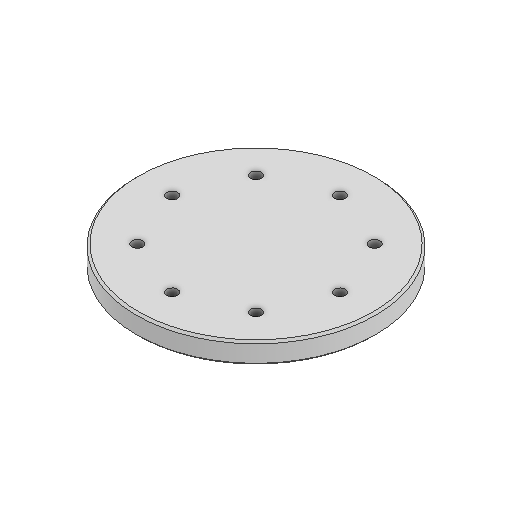
# Autodesk Inventor part: 3DP_PLA_A_Axis_Rotating_Stage_Mounting_Plate
Saved by Autodesk Inventor 2027 (Build 310192060, 192F)
## iProperties
Created: 2026-01-06
Part Number: 3DP_PLA_A_Axis_Rotating_Stage_Mounting_Plate
Material: Generic
Document SubType Name: Modeling
Designer: User
Density: 1 g/cm^3
Appearance: Default
Author: User
Autodesk Inventor part; units mm, degrees
ref_plane "YZ Plane" through (0, 0, 0) normal (1, 0, 0) x (0, 1, 0)
ref_plane "XZ Plane" through (0, 0, 0) normal (0, 1, 0) x (-1, 0, 0)
ref_plane "XY Plane" through (0, 0, 0) normal (0, 0, 1) x (1, 0, 0)
sketch "Sketch1" plane through (0, 0, 0) normal (0, 1, 0) x (-1, 0, 0)
  circle A0 centre (0, 0) radius 57
  dimension "d0" = 114
  constraints: 1 centre point, 1 coincident
  measures "d0" diameter of A0
extrude "Extrusion1" add sketch "Sketch1" along normal blind 10
chamfer "Chamfer1" distance 1 angle 45 1 edges at (57, 10, 0)
chamfer "Chamfer2" distance 1 angle 45 1 edges at (57, 0, 0)
sketch "Sketch2" plane through (0, 0, 0) normal (0, -1, 0) x (1, 0, 0)
  circle A0 centre (0, 0) radius 56 projected
  point P0 (40, 0)
  point P1 (28.2843, 28.2843)
  point P2 (0, 40)
  point P3 (-28.2843, 28.2843)
  point P4 (-40, 0)
  point P5 (-28.2843, -28.2843)
  point P6 (0, -40)
  point P7 (28.2843, -28.2843)
  dimension "d9" = 40
  dimension "d12" = 360
  constraints: 9 other
  measures "d9" distance of point (0, 0) point (40, 0)
hole "Hole1" at (40, 0, 0) at (28.2843, 0, 28.2843) at (0, 0, 40) at (-28.2843, 0, 28.2843) at (-40, 0, 0) at (-28.2843, 0, -28.2843) at (0, 0, -40) at (28.2843, 0, -28.2843) direction (0, 1, 0) diameter 5.2 end through all
sketch "Sketch3" plane through (0, 0, 0) normal (0, -1, 0) x (1, 0, 0)
  circle A0 centre (28.2843, -28.2843) radius 2.6 projected
  circle A1 centre (0, -40) radius 2.6 projected
  circle A2 centre (-28.2843, -28.2843) radius 2.6 projected
  circle A3 centre (-40, 0) radius 2.6 projected
  circle A4 centre (-28.2843, 28.2843) radius 2.6 projected
  circle A5 centre (0, 40) radius 2.6 projected
  circle A6 centre (28.2843, 28.2843) radius 2.6 projected
  circle A7 centre (40, 0) radius 2.6 projected
  circle A8 centre (0, 0) radius 56 projected
  line L0 (44.25, -2.4537) -> (40, -4.9075)
  line L1 (40, -4.9075) -> (35.75, -2.4537)
  line L2 (35.75, -2.4537) -> (35.75, 2.4537)
  line L3 (35.75, 2.4537) -> (40, 4.9075)
  line L4 (40, 4.9075) -> (44.25, 2.4537)
  line L5 (44.25, 2.4537) -> (44.25, -2.4537)
  dimension "d21" = 8.5
  constraints: 12 end point, 1 coincident, 13 other
  measures "d21" distance between parallel lines of L2 L5
extrude "Extrusion2" cut sketch "Sketch3" against normal blind 5 contours L0 L1 L2 L3 L4 L5
pattern_circular "Circular Pattern1" count 8 over 360 about axis through (0, 0, 0) along (0, 1, 0) of "Extrusion2"
body "Solid1"
